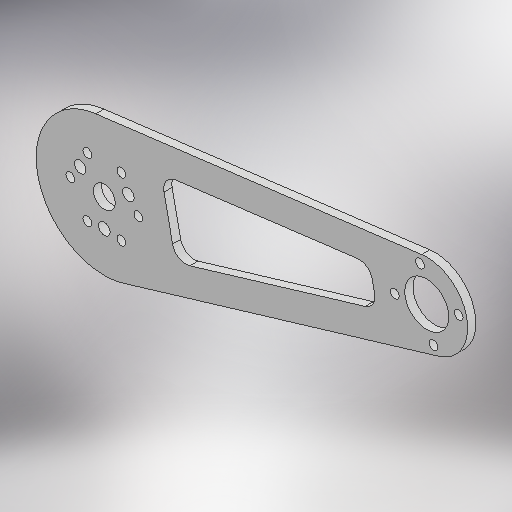
# Autodesk Inventor part: CP4.0_base-arm1
Saved by Autodesk Inventor 2025.3 (Build 293356030, 356C)
## iProperties
Created: 2026-01-04
Part Number: CP4.0_base-arm1
Material: 一般
Document SubType Name: Sheet Metal
Designer: ibuki_ono
Density: 1 g/cm^3
Sheet Metal Rule: Default_mm
Appearance: 既定
Author: ibuki_ono
Autodesk Inventor part; units mm, degrees
ref_plane "YZ Plane" through (0, 0, 0) normal (1, 0, 0) x (0, 1, 0)
ref_plane "XZ Plane" through (0, 0, 0) normal (0, 1, 0) x (-1, 0, 0)
ref_plane "XY Plane" through (0, 0, 0) normal (0, 0, 1) x (1, 0, 0)
sketch "スケッチ1" plane through (0, 0, 0) normal (0, 0, 1) x (1, 0, 0)
  circle A0 centre (0, 0) radius 25
  circle A1 centre (118.3892, 25) radius 15
  line L0 (-3.1261, 24.8038) -> (116.5135, 39.8823)
  line L1 (122.6907, 10.63) -> (7.1692, -23.95)
  dimension "d0" = 50
  dimension "d1" = 30
  dimension "d2" = 121
  dimension "d34" = 25
  measures "d0" diameter of A0
  measures "d1" diameter of A1
  measures "d2" distance of point (0, 0) A1.centre
  measures "d34" vertical distance of A1.centre point (0, 0)
extrude "プレート1" add sketch "スケッチ1" along normal blind 3
sketch "スケッチ2" plane through (0, 0, 3) normal (0, 0, 1) x (1, 0, 0)
  line L0 (0, 0) -> (12.5, 0) construction
  line L1 (0, 0) -> (12.5, 0) construction
  dimension "d4" = 12.5
  dimension "d5" = 0
  constraints: 4 end point, 2 horizontal, 1 coincident, 1 collinear
  measures "d4" distance of L0.start L0.end
  measures "d5" distance between parallel lines of L0 L1
hole "穴1" at (12.5, 0, 3) direction (0, 0, -1) diameter 3.2 end through all
pattern_circular "円形状パターン1" count 6 over 360 about axis through (0, 0, -10) along (0, 0, 1) of "穴1"
sketch "スケッチ3" plane through (0, 0, 3) normal (0, 0, 1) x (1, 0, 0)
  line L0 (0, 0) -> (8.8335, 5.1) construction
  line L1 (0, 0) -> (10.2, 0) construction
  dimension "d16" = 10.2
  dimension "d17" = 30
  constraints: 4 end point, 1 coincident, 1 equal length, 1 horizontal
  measures "d16" distance of L0.start L0.end
  measures "d17" angle of L1 L0
hole "穴2" at (8.8335, 5.1, 3) direction (0, 0, -1) diameter 4.2 end through all
pattern_circular "円形状パターン2" count 3 over 360 about axis through (0, 0, -10) along (0, 0, 1) of "穴2"
sketch "スケッチ4" plane through (0, 0, 3) normal (0, 0, 1) x (1, 0, 0)
  circle A0 centre (0, 0) radius 4
  dimension "d28" = 8
  constraints: 1 centre point, 1 coincident
  measures "d28" diameter of A0
extrude "押し出し1" cut sketch "スケッチ4" against normal blind 10
sketch "スケッチ5" plane through (0, 0, 3) normal (0, 0, 1) x (1, 0, 0)
  arc A0 (122.6907, 10.63) -> (116.5135, 39.8823) centre (118.3892, 25) ccw projected
  circle A1 centre (118.3892, 25) radius 8.05
  point P0 (0, 0)
  dimension "d31" = 16.1
  constraints: 1 centre point, 1 coincident
  measures "d31" diameter of A1
extrude "押し出し2" cut sketch "スケッチ5" against normal through all
sketch "スケッチ6" plane through (0, 0, 3) normal (0, 0, 1) x (1, 0, 0)
  circle A0 centre (118.3892, 25) radius 8.05 projected
  circle A1 centre (118.3892, 25) radius 12 construction
  circle A2 centre (0, 0) radius 4 construction
  line L0 (0, 0) -> (130.1303, 27.4793) construction
  dimension "d35" = 24
  constraints: 2 coincident, 2 end point, 1 point on line, 3 other
hole "穴3" at (130.1303, 27.4793, 3) direction (0, 0, -1) diameter 3.2 end through all
pattern_circular "円形状パターン3" count 4 over 360 about axis through (118.3892, 25, 3) along (0, 0, -1) of "穴3"
sketch "スケッチ7" plane through (0, 0, 3) normal (0, 0, 1) x (1, 0, 0)
  line L0 (20.7836, 17.7381) -> (97.4414, 27.3995)
  line L1 (97.4414, 27.3995) -> (100.2, 14.3361)
  line L2 (100.2, 14.3361) -> (26.1808, -7.8207)
  line L3 (26.1808, -7.8207) -> (20.7836, 17.7381)
  line L4 (-3.1261, 24.8038) -> (116.5135, 39.8823) projected
  line L5 (122.6907, 10.63) -> (7.1692, -23.95) projected
  circle A0 centre (118.3892, 25) radius 8.05 projected
  circle A1 centre (0, 0) radius 4 construction
  line L6 (0, 0) -> (118.3892, 25) construction
  dimension "d46" = 10
  dimension "d47" = 10
  dimension "d48" = 20
  dimension "d49" = 24
  constraints: 10 end point, 2 parallel, 2 perpendicular
  measures "d46" distance between parallel lines of L0 L4
  measures "d47" distance between parallel lines of L5 L2
  measures "d48" distance from line of L6.end L1
  measures "d49" distance from line of L3 point (0, 0)
extrude "押し出し3" cut sketch "スケッチ7" against normal blind 10 contours L0 L1 L2 L3
fillet "フィレット1" radius 5 4 edges at (20.7836, 17.7381, 1.5) (97.4414, 27.3995, 1.5) (100.2, 14.3361, 1.5) (26.1808, -7.8207, 1.5)
equation "\"d11\" = Thickness"
equation "\"d41\" = Thickness"
equation "\"d47\" = d46"
equation "\"d3\" = Thickness"
equation "\"BendRadius\" = Thickness"
equation "\"BendReliefWidth\" = Thickness"
equation "\"BendReliefDepth\" = 0.5 * Thickness"
equation "\"CornerReliefSize\" = 4 * Thickness"
equation "\"MinimumRemnant\" = 2 * Thickness"
equation "\"TransitionRadius\" = BendRadius"
equation "\"JacobiRadiusSize\" = BendRadius"
equation "\"GapSize\" = Thickness"
equation "\"Thickness\" = 3"
